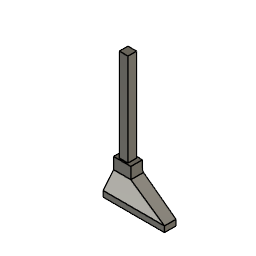
Front Right Frame Mount (Autodesk Fusion 360 design; units mm, degrees)
Autodesk Fusion 360 part; units mm, degrees
sketch "Sketch1" plane through (0, 0, 0) normal (0, 1, 0) x (1, 0, 0)
  line L0 (0, 0) -> (-25.4, 0)
  line L1 (-25.4, 0) -> (-25.4, -3.175)
  line L2 (-25.4, -3.175) -> (0, -3.175)
  line L3 (0, -3.175) -> (0, 0)
  line L4 (-25.4, 0) -> (-33.655, 0)
  line L5 (-33.655, 0) -> (-33.655, -3.175)
  line L6 (-33.655, -3.175) -> (-25.4, -3.175)
  line L7 (-25.4, -3.175) -> (-25.4, 0)
  line L8 (-26.035, -3.175) -> (-15.24, -28.575)
  line L9 (-15.24, -28.575) -> (-5.715, -28.575)
  line L10 (-5.715, -28.575) -> (-9.525, -3.175)
  line L11 (-15.24, -28.575) -> (-5.715, -28.575)
  line L12 (-5.715, -28.575) -> (-5.715, -34.925)
  line L13 (-5.715, -34.925) -> (-15.24, -34.925)
  line L14 (-15.24, -34.925) -> (-15.24, -28.575)
  dimension "d3" = 33.655
  dimension "d4" = 8.255
  dimension "d5" = 25.4
  dimension "d6" = 3.175
  dimension "d7" = 3.175
  dimension "d26" = 6.35
  dimension "d27" = 25.4
  dimension "d28" = 9.525
  dimension "d30" = 16.51
  dimension "d31" = 3.81
  dimension "d32" = 9.525
  constraint horizontal L0
  constraint vertical L1
  constraint horizontal L2
  constraint vertical L3
  constraint coincident L0.start L3.end
  constraint horizontal L4
  constraint vertical L5
  constraint horizontal L6
  constraint vertical L7
  constraint coincident L2 L8.start
  constraint perpendicular L1 L9
  constraint coincident L2 L10.end
  constraint horizontal L11
  constraint vertical L12
  constraint horizontal L13
  constraint vertical L14
  constraint horizontal L0.end L4.end
  measures "d3" distance of L3 L5
  measures "d4" distance of L0.end L4.end
  measures "d5" distance of L0.start L0.end
  measures "d6" distance of L4.end L5.end
  measures "d7" distance of L0.start L2.end
  measures "d26" distance of L9.end L12.end
  measures "d27" distance of L2 L9
  measures "d28" distance of L12 L14
  measures "d30" distance of L8.start L10.end
  measures "d31" horizontal distance of L10.end L9.end
  measures "d32" distance of L2.end L10.end
extrude "Extrude1" add sketch "Sketch1" along normal blind 19.05 makes body 1
sketch "Sketch2" plane through (0, 0, 3.175) normal (0, 0, 1) x (-1, 0, 0)
  line L0 (33.655, 0) -> (26.035, 0)
  line L1 (0, 0) -> (0, -19.05)
  line L2 (26.035, -19.05) -> (33.655, -19.05)
  line L3 (33.655, -19.05) -> (33.655, 0)
  circle A0 centre (28.8925, -14.2875) radius 2.1971
  circle A1 centre (3.4925, -14.2875) radius 2.1971
  line L4 (26.035, 0) -> (26.035, -19.05)
  line L5 (9.525, 0) -> (0, 0)
  line L6 (0, -19.05) -> (9.525, -19.05)
  line L7 (9.525, -19.05) -> (9.525, 0)
  dimension "d10" = 4.3942
  dimension "d11" = 4.3942
  dimension "d12" = 4.7625
  dimension "d13" = 4.7625
  dimension "d14" = 25.4
  dimension "d15" = 4.7625
  measures "d10" diameter of A0
  measures "d11" diameter of A1
  measures "d12" distance of L2 A0.centre
  measures "d13" distance of L2 A1.centre
  measures "d14" distance of A0.centre A1.centre
  measures "d15" distance of L3 A0.centre
sketch "Sketch5" plane through (0, 0, 34.925) normal (0, 0, 1) x (-1, 0, 0)
  line L0 (15.24, 0) -> (5.715, 0)
  line L1 (5.715, 0) -> (5.715, -19.05)
  line L2 (5.715, -19.05) -> (15.24, -19.05)
  line L3 (15.24, -19.05) -> (15.24, 0)
  line L4 (12.8588, -5.5563) -> (8.0962, -5.5563)
  line L5 (8.0962, -5.5563) -> (8.0962, -0.7937)
  line L6 (8.0962, -0.7937) -> (12.8588, -0.7938)
  line L7 (12.8588, -0.7938) -> (12.8588, -5.5563)
  dimension "d33" = 4.7625
  dimension "d34" = 4.7625
  dimension "d36" = 2.3813
  dimension "d54" = 0.7937
  constraint horizontal L4
  constraint vertical L5
  constraint horizontal L6
  constraint vertical L7
  measures "d33" distance of L4.end L5.end
  measures "d34" distance of L4.start L4.end
  measures "d36" distance of L1 L5
  measures "d54" distance of L0 L6
extrude "Extrude5" add sketch "Sketch5" along normal blind 50.8 contours L4 L5 L6 L7 bodies 1
sketch "Sketch6" plane through (0, 0, 0) normal (0, -1, 0) x (1, 0, 0)
  line L0 (-9.525, 3.175) -> (-5.715, 28.575)
  line L1 (-5.715, 28.575) -> (-5.715, 34.925)
  line L2 (-5.715, 34.925) -> (-15.24, 34.925)
  line L3 (-15.24, 34.925) -> (-15.24, 28.575)
  line L4 (-15.24, 28.575) -> (-26.035, 3.175)
  line L5 (-26.035, 3.175) -> (-33.655, 3.175)
  line L6 (-33.655, 3.175) -> (-33.655, 0)
  line L7 (-33.655, 0) -> (0, 0)
  line L8 (0, 0) -> (0, 3.175)
  line L9 (0, 3.175) -> (-9.525, 3.175)
  line L10 (-21.2358, 6.35) -> (-12.2593, 6.35)
  line L11 (-12.2593, 6.35) -> (-8.9255, 28.575)
  line L12 (-8.9255, 28.575) -> (-11.7902, 28.575)
  line L13 (-11.7902, 28.575) -> (-21.2358, 6.35)
  line L14 (-13.9069, 23.5944) -> (-10.3578, 28.575)
  line L15 (-10.3578, 28.575) -> (-9.0638, 27.6529)
  dimension "d39" = 6.35
  dimension "d40" = 6.35
  dimension "d41" = 3.175
  dimension "d42" = 3.175
  dimension "d43" = 90
  dimension "d44" = 6.1157
  constraint horizontal L10
  constraint parallel L10 L12
  constraint parallel L4 L13
  constraint coincident L10.start L13.end
  constraint parallel L0 L11
  constraint coincident L13 L14.start
  constraint midpoint L12 L14.end
  constraint coincident L11 L15.end
  measures "d39" distance of L7 L10
  measures "d40" distance of L2 L12
  measures "d41" distance of L0 L11
  measures "d42" distance of L4 L13
  measures "d43" angle of L14 L15
  measures "d44" distance of L14.start L14.end
extrude "Extrude6" cut sketch "Sketch6" against normal blind 19.05 contours L10 L11 L13 L14 L15 bodies 1
sketch "Sketch7" plane through (-33.655, 0, 0) normal (-1, 0, 0) x (0, -1, 0)
  line L0 (0, 0) -> (0, 3.175)
  line L1 (0, 3.175) -> (-19.05, 3.175)
  line L2 (-19.05, 3.175) -> (-19.05, 0)
  line L3 (-19.05, 0) -> (0, 0)
  line L4 (0, 0) -> (-19.05, 0)
  line L5 (-19.05, 34.925) -> (0, 34.925)
  line L6 (0, 34.925) -> (0, 0)
  line L7 (0, 0) -> (-19.05, 0)
  line L8 (-19.05, 0) -> (-19.05, 34.925)
  line L9 (-19.05, 0) -> (-12.7, 0)
  line L10 (-12.7, 0) -> (-12.7, 3.175)
  line L11 (-12.7, 3.175) -> (-19.05, 3.175)
  line L12 (-19.05, 3.175) -> (-19.05, 0)
  line L13 (0, 34.925) -> (-6.35, 34.925)
  line L14 (-6.35, 34.925) -> (-6.35, 30.9993)
  line L15 (-6.35, 28.575) -> (0, 28.575)
  line L16 (0, 30.063) -> (0, 34.925)
  arc A0 (-8.1017, 27.1615) -> (-19.05, 3.175) centre (12.7, 3.175) ccw
  arc A1 (-0.7873, 27.3465) -> (-12.7, 3.175) centre (106.5301, -40.565) ccw
  arc A2 (-8.1017, 27.1615) -> (-6.35, 30.9993) centre (-11.43, 30.9993) ccw
  arc A3 (-0.7873, 27.3465) -> (0, 30.063) centre (-5.08, 30.063) ccw
  dimension "d55" = 34.925
  dimension "d56" = 19.05
  dimension "d57" = 6.35
  dimension "d58" = 6.35
  dimension "d59" = 6.35
  dimension "d60" = 127
  dimension "d61" = 5.08
  constraint horizontal L4
  constraint coincident L0.start L3.end
  constraint horizontal L5
  constraint vertical L6
  constraint horizontal L7
  constraint vertical L8
  constraint horizontal L9
  constraint vertical L10
  constraint horizontal L11
  constraint vertical L12
  constraint coincident L1 L10.end
  constraint coincident L2.end L3.start
  constraint horizontal L13
  constraint vertical L14
  constraint horizontal L15
  constraint vertical L16
  constraint tangent L8 A0
  constraint coincident L15.start L14
  constraint coincident L15.start A0
  constraint tangent A0 A2
  constraint tangent L14 A2
  constraint coincident L15.end L16
  constraint coincident L15.end A1
  constraint tangent A1 A3
  constraint tangent L16 A3
  constraint equal A2 A3
  measures "d55" distance of L5.start L2.end
  measures "d56" distance of L5.start L5.end
  measures "d57" distance of L2.end L9.end
  measures "d58" distance of L13.end L15.start
  measures "d59" distance of L15.start L15.end
  measures "d60" radius of A1
  measures "d61" radius of A2
extrude "Extrude7" cut sketch "Sketch7" against normal blind 33.655 contours L0 L1 L3 L4 L6 L7 L10 | L1 L6 L15 A1 A3 | L5 L8 L14 A0 A2 bodies 1
sketch "Sketch8" plane through (0, 0, 0) normal (1, 0, 0) x (0, 1, 0)
  line L0 (12.7, 3.175) -> (12.7, 0)
  line L1 (12.7, 0) -> (19.05, 0)
  line L2 (19.05, 0) -> (19.05, 3.175)
  line L3 (19.05, 3.175) -> (12.7, 3.175)
  line L4 (19.05, 0) -> (0, 0)
  line L5 (0, 0) -> (0, 28.6288)
  line L6 (0, 28.6288) -> (19.05, 28.6288)
  line L7 (19.05, 28.6288) -> (19.05, 0)
  dimension "d64" = 28.6288
  dimension "d65" = 19.05
  constraint horizontal L4
  constraint vertical L5
  constraint horizontal L6
  constraint vertical L7
  constraint coincident L1.end L2.start
  measures "d64" distance of L4.end L5.end
  measures "d65" distance of L5.end L6.end
extrude "Extrude8" cut sketch "Sketch8" against normal blind 45.72 contours L0 L3 L4 L5 L6 L7 bodies 1 makes body 2 at (-11.2713, 5.5562, 51.8583)
loft "Loft1" add section 1 face at (-8.89, 2.3123, 28.6288) section 2 face at (-11.2183, 16.9333, 3.175) on bodies 1 2 bodies 1 2
equation "d3 = 1.375 in - 0.05 in"
equation "d4 = 0.375 in - 0.05 in"
equation "d12 = ( 0.375 / 2 ) * 1 in"
equation "d13 = ( 3 / 16 ) * 1 in"
equation "d15 = ( 3 / 16 ) * 1 in"
equation "d28 = ( 3 / 8 ) * 1 in"
equation "d33 = ( 3 / 16 ) * 1 in"
equation "d34 = ( 3 / 16 ) * 1 in"
equation "d36 = ( 3 / 32 ) * 1 in"
equation "d54 = ( 1 / 32 ) * 1 in"
